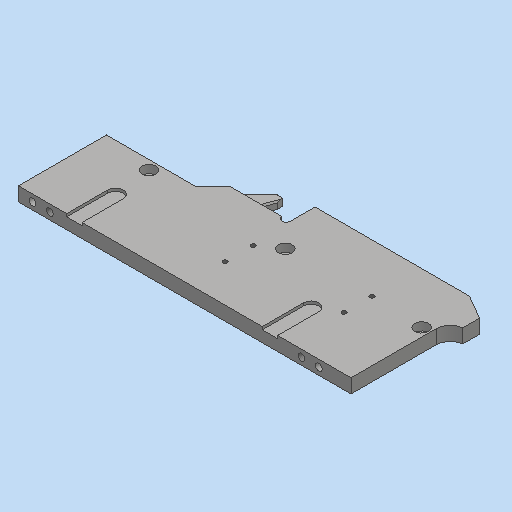
# Autodesk Inventor part: MM0948AN100_G01_102
Saved by Autodesk Inventor 2023.3 (Build 273359000, 359)
## iProperties
Part Number: MM0948AN100_G01_102
Material: 1.2842 90MnCrV8
Description: =<RBPARTNOTITLE2>
Document SubType Name: Modeling
Designer: ric7an
Mass: 1482.65 g
Surface Area: 479.824 cm^2
Volume: 188.872 cm^3
Density: 7.85 g/cm^3
Appearance: Stahl - normal AnP
Created: 2023-03-23
RBDOCUMENTTYPE: DRF
RBDOCUMENTVERSION: 00
RBDRAWINGMAINSCALE: 1:1
RBDRAWINGMISSINGSPEC: --
RBDRAWINGVOLUME: --
RBGBEDGESIN1: +0,5
RBGBEDGESIN2: +0,2
RBGBEDGESOUT1: -0,3
RBGBEDGESOUT2: -0,1
RBMATERIAL: =<Material>
RBMATMEETS: --
RBMATNO: =<Part Number>
RBPARTMADEOF: 10 x 93 x 247 (FM)
RBPARTNO: SIEHE MNR
RBPARTNOTITLE1: manufactured part
RBPARTNOTITLE2: Anfertigungsteil
RBPARTSAFETYINDICATOR: --
RBSURFACE: plasma nitrided 550 HV, Nht 0,2 + 0,1
RBSURFACE2: plasmanitriert 550 HV, Nht 0,2 + 0,1
RBZEDGESNORM: ISO13715:2002-06
RBZGENDIMCLASS: m
RBZGENDIMNORM: ISO 2768-1:1989-11
RBZGENGEOCLASS: H
RBZGENGEONORM: ISO 2768-2:1989-11
RBZSURFACENORM: ISO13D2:2002-02
RBZTOLERANCENORM: ISO 14405-1:2010-12
AnP_Material: =<Material>
AnP_TemplVers: 20190222
AnP_Kategorie: 1
MaxAbmaße: 10 x 93 x 247 (FM)
AnP_Kommentar_aktuell: =<Comments>
AnP_Material_aktuell: =<Material>
Author: FH/Wi
Keywords: =<RBPARTMADEOF>
Comments: =<RBSURFACE2>
Revision Number: 01
Autodesk Inventor part; units mm, degrees
ref_plane "YZ Plane" through (0, 0, 0) normal (1, 0, 0) x (0, 1, 0)
ref_plane "XZ Plane" through (0, 0, 0) normal (0, 1, 0) x (-1, 0, 0)
ref_plane "XY Plane" through (0, 0, 0) normal (0, 0, 1) x (1, 0, 0)
sketch "Skizze1" plane through (0, 0, 0) normal (0, 0, 1) x (1, 0, 0)
  line L0 (-112.5, 0) -> (125.5, 0)
  line L1 (125.5, 0) -> (125.5, 61)
  line L2 (125.5, 93) -> (-112.5, 93)
  line L3 (-112.5, 93) -> (-112.5, 0)
  line L4 (0, 111.6) -> (0, -18.6) projected
  line L5 (-164.5, 0) -> (199.5, 0) projected
  line L6 (125.5, 93) -> (134.5, 93)
  line L7 (134.5, 93) -> (134.5, 71)
  line L8 (134.5, 71) -> (135.5, 71)
  line L9 (125.5, 61) -> (125.5, 93)
  line L10 (147.5, 93) -> (147.5, 71)
  arc A0 (135.5, 71) -> (125.5, 61) centre (135.5, 61) ccw
  line L11 (134.5, 71) -> (134.5, 70.9499)
  point P0 (0, 0)
  point P1 (112.5, 71)
  point P2 (132.5, 71)
  point P3 (135.5, 71)
  dimension "d0" = 93
  dimension "d1" = 238
  dimension "d39" = 9
  dimension "d40" = 22
  dimension "d141" = 22
  dimension "d142" = 10
  dimension "d151" = 112.5
  constraints: 20 end point, 4 parallel, 4 point on circle, 3 point on line, 2 horizontal, 2 perpendicular, 2 tangent, 2 vertical, 1 centre point, 1 collinear
  measures "d0" distance of L0.end L2.start
  measures "d1" distance of L2.start L2.end
  measures "d39" distance of L2.start L6.end
  measures "d40" distance of L6.end L7.end
  measures "d141" distance between parallel lines of L1 L10
  measures "d142" radius of A0
  measures "d151" distance between parallel lines of L4 L3
extrude "Extrusion1" add sketch "Skizze1" along normal blind 10 contours L3 L2 L4 L0 | L4 L2 L9 L1 L0 | L9 L6 L7 L11 A0
sketch "Skizze3" plane through (0, 0, 10) normal (0, 0, 1) x (1, 0, 0)
  line L0 (0, 111.6) -> (0, -18.6) projected
  line L1 (-161.9, 0) -> (183.9, 0) projected
  point P0 (0, 0)
  point P1 (-75.5, 56.5)
  point P2 (119.5, 56.5)
  point P3 (22, 56.5)
  dimension "d5" = 56.5
  dimension "d51" = 97.5
  dimension "d145" = 97.5
  dimension "d146" = 75.5
  constraints: 2 horizontal alignment
  measures "d5" distance from line of L1 point (-75.5, 56.5)
  measures "d51" distance of point (22, 56.5) point (-75.5, 56.5)
  measures "d145" distance of point (119.5, 56.5) point (22, 56.5)
  measures "d146" distance from line of L0 point (-75.5, 56.5)
hole "Bohrung1" at (-75.5, 56.5, 10) at (119.5, 56.5, 10) at (22, 56.5, 10) direction (0, 0, -1) diameter 5.5 end through all counterbore diameter 10 counterbore depth 5.7 clearance for "Inbusschraube ISO 4762  versenkt" size "M5" standard "ISO"
sketch "Skizze4" plane through (-112.5, 0, 0) normal (0, -1, 0) x (1, 0, 0)
  line L0 (112.5, 12) -> (112.5, -2) projected
  line L1 (-49.4, 0) -> (296.4, 0) projected
  point P0 (112.5, 0)
  point P1 (22.5, 5)
  point P2 (202.5, 5)
  dimension "d13" = 5
  dimension "d14" = 180
  constraints: 1 symmetric about line
  measures "d13" distance from line of L1 point (202.5, 5)
  measures "d14" distance of point (202.5, 5) point (22.5, 5)
hole "Bohrung2" at (-90, 0, 5) at (90, 0, 5) direction (0, 1, 0) diameter 4.917 depth 17.1 tip angle 118 thread size "M6x1" designation "M6" class "6H" standard "ISO Metric profile"
sketch "Skizze7" plane through (0, 0, 10) normal (0, 0, 1) x (1, 0, 0)
  circle A0 centre (-75.5, 56.5) radius 5 projected
  line L0 (-112.5, 0) -> (125.5, 0) projected
  line L1 (125.5, 0) -> (125.5, 61) projected
  line L2 (134.5, 93) -> (-112.5, 93) projected
  line L3 (-112.5, 93) -> (-112.5, 0) projected
  line L4 (-112.5, 93) -> (6.75, 93)
  line L5 (6.75, 93) -> (6.75, 63)
  line L6 (-49.4926, 63) -> (-112.5, 63)
  line L7 (-112.5, 63) -> (-112.5, 93)
  line L8 (6.75, 63) -> (-13.25, 63)
  line L9 (-13.25, 63) -> (-13.25, 75.3)
  line L10 (-15.588, 75.3) -> (6.75, 75.3)
  line L11 (6.75, 75.3) -> (6.75, 63)
  arc A1 (0.75, 75.3) -> (6.75, 75.3) centre (3.75, 75.3) ccw
  line L12 (-47.3713, 63.8787) -> (-19.25, 92)
  line L13 (-19.25, 92) -> (-15.25, 92)
  line L14 (-15.25, 92) -> (-15.25, 88)
  arc A2 (-49.4926, 63) -> (-47.3713, 63.8787) centre (-49.4926, 66) ccw
  line L15 (-15.25, 88) -> (-18.4071, 79.3261)
  arc A3 (-18.4071, 79.3261) -> (-15.588, 75.3) centre (-15.588, 78.3) ccw
  arc A4 (134.5, 70.9499) -> (125.5, 61) centre (135.5, 61) ccw projected
  line L16 (134.5, 70.9499) -> (134.5, 93) projected
  line L17 (0, 111.6) -> (0, -18.6) projected
  circle A5 centre (119.5, 56.5) radius 5 projected
  point P0 (0, 0)
  point P1 (-48.25, 63)
  point P2 (6.75, 93)
  point P3 (-19.8724, 75.3)
  point P4 (6.75, 75.3)
  dimension "d37" = 30
  dimension "d53" = 12.3
  dimension "d57" = 6
  dimension "d117" = 1
  dimension "d118" = 135
  dimension "d119" = 22
  dimension "d121" = 20
  dimension "d123" = 3
  dimension "d126" = 3
  dimension "d127" = 20
  dimension "d128" = 4
  dimension "d143" = 4
  dimension "d147" = 6.75
  constraints: 24 end point, 8 point on line, 6 point on circle, 4 parallel, 4 tangent, 3 centre point, 3 horizontal, 3 perpendicular
  measures "d37" distance of L4.end L5.end
  measures "d53" distance between parallel lines of L6 L10
  measures "d57" distance of L10.end A1.start
  measures "d117" distance between parallel lines of L13 L2
  measures "d118" angle of L6 L12
  measures "d119" distance between parallel lines of L5 L14
  measures "d121" distance between parallel lines of L5 L9
  measures "d123" radius of A2
  measures "d126" radius of A3
  measures "d127" angle of L15 L14
  measures "d128" distance from line of L13 L14.end
  measures "d143" distance from line of L12.end L14
  measures "d147" distance between parallel lines of L17 L5
extrude "Extrusion4" cut sketch "Skizze7" against normal through all contours L3 L2 L17 L10 A3 L15 L14 L13 L12 A2 L6 | L17 L2 L5 L10 | A1 L10
sketch "Skizze10" plane through (-5.8304, 75.3, 10) normal (0, 1, 0) x (1, 0, 0)
  line L0 (12.5804, 10) -> (12.5804, 0) projected
  line L1 (-9.7576, 10) -> (6.5804, 10) projected
  point P0 (5.8304, 10)
  point P1 (0.0804, 5)
  point P2 (0, 10)
  dimension "d58" = 12.5
  dimension "d59" = 5
  measures "d58" distance from line of L0 point (0.08, 5)
  measures "d59" distance from line of point (0.08, 5) L1
hole "Bohrung3" at (-5.75, 75.3, 5) direction (0, -1, 0) diameter 2.459 depth 8.8 tip angle 118 thread size "M3x0.5" designation "M3" class "6H" standard "ISO Metric profile"
sketch "Skizze15" plane through (0, 0, 10) normal (0, 0, -1) x (-1, 0, 0)
  line L0 (-6.75, 92) -> (35.95, 92)
  line L1 (35.95, 92) -> (35.95, 75.3)
  line L2 (35.95, 75.3) -> (-6.75, 75.3)
  line L3 (-6.75, 75.3) -> (-6.75, 92)
  line L4 (4.5205, 75.3) -> (6.9795, 75.3) projected
  line L5 (15.588, 75.3) -> (-0.75, 75.3) projected
  line L6 (-0.75, 75.3) -> (15.588, 75.3) projected
  line L7 (-6.75, 75.3) -> (-6.75, 93) projected
  line L8 (-6.75, 93) -> (-6.75, 75.3) projected
  line L9 (47.3713, 63.8787) -> (19.25, 92) projected
  line L10 (19.25, 92) -> (47.3713, 63.8787) projected
  line L11 (15.588, 75.3) -> (-0.75, 75.3) projected
  line L12 (47.3713, 63.8787) -> (19.25, 92) projected
  point P0 (0, 0)
  point P1 (34.81, 81.3)
  constraints: 8 end point, 2 collinear, 2 parallel, 2 point on line, 1 horizontal, 1 perpendicular
extrude "Extrusion7" cut sketch "Skizze15" along normal blind 5 contours L0 L9 L2 L3
sketch "Skizze12" plane through (0, 0, 0) normal (0, 0, -1) x (-1, 0, 0)
  line L0 (112.5, 0) -> (-125.5, 0) projected
  line L1 (-125.5, 0) -> (-125.5, 61) projected
  line L2 (0, -18.6) -> (0, 111.6) projected
  point P0 (0, 0)
  point P1 (-82.5, 58)
  point P2 (-82.5, 38)
  point P3 (-8.5, 47)
  point P4 (-8.5, 27)
  point P5 (-47.5, 68)
  point P6 (-47.5, 48)
  point P7 (16.5, 50)
  point P8 (16.5, 30)
  dimension "d78" = 20
  dimension "d79" = 38
  dimension "d88" = 27
  dimension "d89" = 20
  dimension "d110" = 20
  dimension "d112" = 48
  dimension "d114" = 20
  dimension "d115" = 25
  dimension "d116" = 30
  dimension "d148" = 82.5
  dimension "d149" = 47.5
  dimension "d150" = 8.5
  constraints: 4 vertical alignment
  measures "d78" distance of point (-82.5, 38) point (-82.5, 58)
  measures "d79" distance from line of L0 point (-82.5, 38)
  measures "d88" distance from line of L0 point (-8.5, 27)
  measures "d89" distance of point (-8.5, 27) point (-8.5, 47)
  measures "d110" distance of point (-47.5, 48) point (-47.5, 68)
  measures "d112" distance from line of L0 point (-47.5, 48)
  measures "d114" distance of point (16.5, 30) point (16.5, 50)
  measures "d115" horizontal distance of point (16.5, 30) point (-8.5, 27)
  measures "d116" distance from line of L0 point (16.5, 30)
  measures "d148" distance from line of L2 point (-82.5, 58)
  measures "d149" distance from line of L2 point (-47.5, 68)
  measures "d150" distance from line of point (-8.5, 47) L2
hole "Bohrung5" at (82.5, 58, 0) at (82.5, 38, 0) at (8.5, 47, 0) at (8.5, 27, 0) direction (0, 0, 1) diameter 3.242 end through all thread size "M4x0.7" designation "M4" class "6H" standard "ISO Metric profile"
sketch "Skizze13" plane through (-112.5, 0, 0) normal (0, -1, 0) x (1, 0, 0)
  line L0 (112.5, 12) -> (112.5, -2) projected
  line L1 (-49.4, 0) -> (296.4, 0) projected
  circle A0 centre (22.5, 5) radius 2.4585 projected
  circle A1 centre (202.5, 5) radius 2.4585 projected
  point P0 (112.5, 0)
  point P1 (10, 5)
  point P2 (215, 5)
  dimension "d91" = 205
  constraints: 2 horizontal alignment, 1 symmetric about line
  measures "d91" distance of point (215, 5) point (10, 5)
hole "Bohrung6" at (-102.5, 0, 5) at (102.5, 0, 5) direction (0, 1, 0) diameter 5 depth 15 tip angle 118
chamfer "Fase1" distance 1 angle 45 2 edges at (-16.8285, 83.663, 5) (-18.0454, 76.5793, 5)
chamfer "Fase2" distance 0.5 angle 45 1 edges at (-15.25, 92, 2.5)
chamfer "Fase3" distance 10 angle 60 1 edges at (134.5, 93, 5) measured on face at (134.5, 92.5, 5)
sketch "Skizze16" plane through (0, 0, 10) normal (0, 0, 1) x (1, 0, 0)
  line L0 (-112.5, 0) -> (125.5, 0) projected
  line L1 (-112.5, 63) -> (-112.5, 0) projected
  line L2 (-67, 0) -> (-78, 0)
  line L3 (-78, 0) -> (-78, 35)
  line L4 (-78, 35) -> (-67, 35)
  line L5 (-67, 35) -> (-67, 0)
  line L6 (73, 0) -> (62, 0)
  line L7 (62, 0) -> (62, 35)
  line L8 (62, 35) -> (73, 35)
  line L9 (73, 35) -> (73, 0)
  point P0 (0, 0)
  point P1 (-72.5, 35)
  point P2 (67.5, 35)
  dimension "d152" = 40
  dimension "d153" = 140
  dimension "d154" = 11
  dimension "d155" = 11
  dimension "d156" = 35
  constraints: 16 end point, 4 parallel, 2 horizontal, 2 midpoint, 2 perpendicular, 2 point on line, 1 collinear
  measures "d152" distance from line of point (-72.5, 35) L1
  measures "d153" distance of point (67.5, 35) point (-72.5, 35)
  measures "d154" distance of L3.end L4.end
  measures "d155" distance of L7.end L8.end
  measures "d156" distance of L2.end L3.end
extrude "Extrusion8" cut sketch "Skizze16" against normal blind 2
fillet "Rundung3" radius 5.5 4 edges at (-78, 35, 9) (-67, 35, 9) (73, 35, 9) (62, 35, 9)
equation "\"d89\" = d78"
equation "\"d110\" = d78"
equation "\"d114\" = d78"
